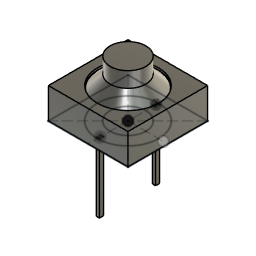
KAP140_LCD v14 (Autodesk Fusion 360 archive; units mm, degrees)
design "8x8 Tactile Silicon Button"
Autodesk Fusion 360 part; units mm, degrees
sketch "Sketch1" plane through (0, 0, 0) normal (0, 0, 1) x (1, 0, 0)
  circle A0 centre (0, 0) radius 1.75
  line L0 (3.9, 3.9) -> (-3.9, 3.9)
  line L1 (-3.9, 3.9) -> (-3.9, -3.9)
  line L2 (-3.9, -3.9) -> (3.9, -3.9)
  line L3 (3.9, -3.9) -> (3.9, 3.9)
  line L4 (3.9, 3.9) -> (-3.9, -3.9) construction
  line L5 (-3.9, 3.9) -> (3.9, -3.9) construction
  circle A1 centre (0, 0) radius 3
  line L6 (0, 3.9) -> (0, -3.9) construction
  line L7 (0.15, 2.55) -> (-0.15, 2.55)
  line L8 (-0.15, 2.55) -> (-0.15, 2.95)
  line L9 (-0.15, 2.95) -> (0.15, 2.95)
  line L10 (0.15, 2.95) -> (0.15, 2.55)
  line L11 (0.15, 2.55) -> (-0.15, 2.95) construction
  line L12 (-0.15, 2.55) -> (0.15, 2.95) construction
  line L13 (0, 0) -> (3.4526, 0) construction
  line L14 (-0.15, -2.95) -> (0.15, -2.95)
  line L15 (0.15, -2.95) -> (0.15, -2.55)
  line L16 (0.15, -2.55) -> (-0.15, -2.95) construction
  line L17 (-0.15, -2.55) -> (-0.15, -2.95)
  line L18 (-0.15, -2.55) -> (0.15, -2.95) construction
  line L19 (0.15, -2.55) -> (-0.15, -2.55)
  point P0 (0, 2.75)
  point P1 (0, -2.75)
  dimension "d1" = 3.5
  dimension "d2" = 7.8
  dimension "d3" = 7.8
  dimension "d4" = 6
  dimension "d8" = 0.3
  dimension "d9" = 0.4
  dimension "d10" = 2.55
  constraint coincident A0.centre A1.centre
  constraint horizontal L0
  constraint perpendicular L0 L1
  constraint parallel L0 L2
  constraint parallel L1 L3
  constraint coincident L4 A0.centre
  constraint coincident L5 A0.centre
  constraint concentric A0 A1
  constraint midpoint L0 L6.start
  constraint midpoint L2 L6.end
  constraint horizontal L7
  constraint perpendicular L7 L8
  constraint parallel L7 L9
  constraint parallel L8 L10
  constraint coincident L11 P0
  constraint coincident L12 P0
  constraint coincident L6 P0
  constraint horizontal L13
  constraint symmetric L7.start L13 L15.end
  constraint symmetric L7.end L13 L17.start
  constraint symmetric L8.end L13 L14.start
  constraint symmetric L9.end L13 L14.end
  constraint symmetric P0 L13 P1
  measures "d1" diameter of A0
  measures "d2" distance of L1.end L2.end
  measures "d3" distance of L0.end L1.end
  measures "d4" diameter of A1
  measures "d8" distance of L8.end L9.end
  measures "d9" distance of L7.end L8.end
  measures "d10" vertical distance of A0.centre L7.start
extrude "Extrude1" add sketch "Sketch1" along normal blind 3 contours L0 L1 L2 L3
extrude "Extrude2" add sketch "Sketch1" along normal blind 2.8 contours A1 | L7 L8 L9 L10 | L14 L15 L17 L19
extrude "Extrude3" add sketch "Sketch1" along normal blind 5.5 contours A0
chamfer "Chamfer1" distance 1.2 angle 45 1 edges at (-1.6316, 0.6328, 2.8)
extrude "Extrude4" add sketch "Sketch1" against normal blind 6.7 contours L7 L8 L9 L10 | L14 L15 L17 L19
equation "d10 = ( 5.1 / 2 ) * 1 mm"
